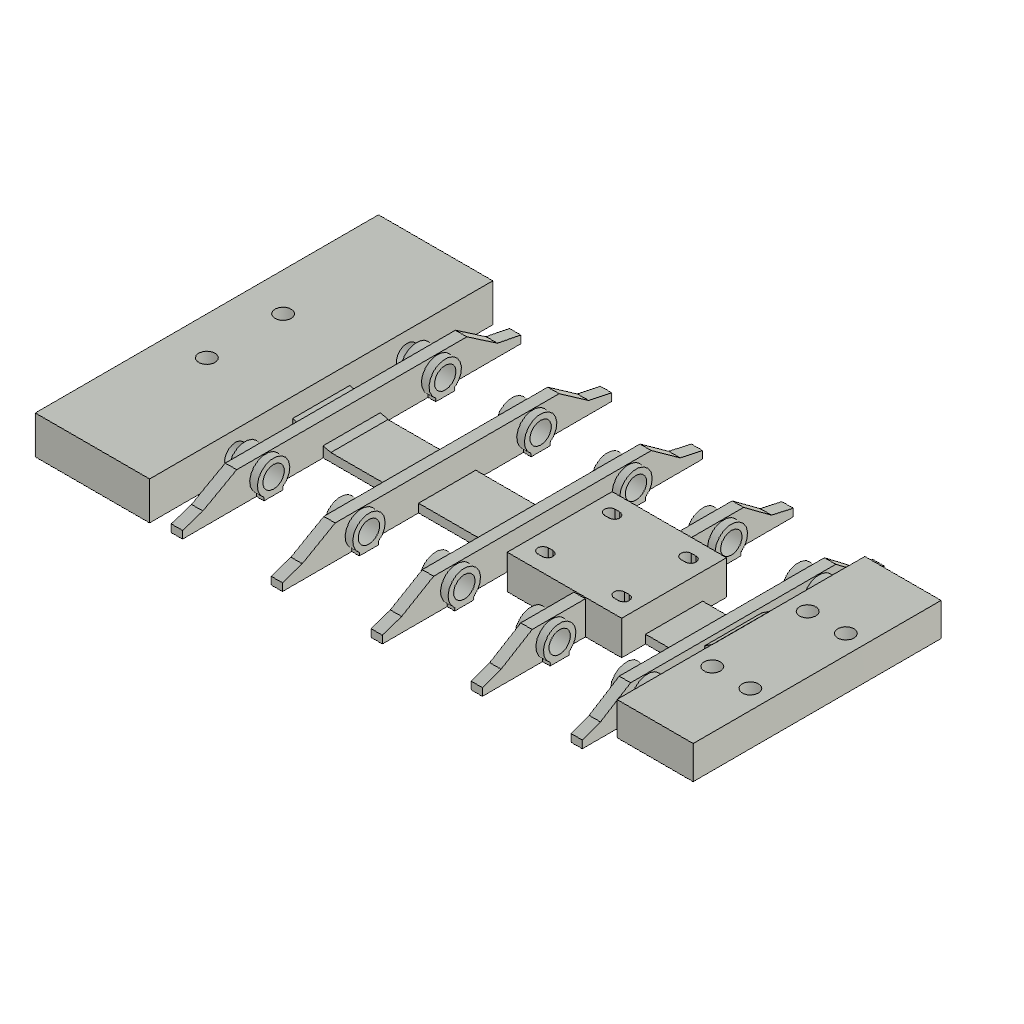
wing (Autodesk Fusion 360 design; units mm, degrees)
part number: 2026-10-10-16-37-37-965
Autodesk Fusion 360 part; units mm, degrees
sketch "Root tongue sketch" plane through (0, 0, 0) normal (0, 0, 1) x (1, 0, 0)
  line L0 (0, -36) -> (24, -36)
  line L1 (24, -36) -> (24, 36)
  line L2 (24, 36) -> (0, 36)
  line L3 (0, 36) -> (0, -36)
extrude "Root tongue" add sketch "Root tongue sketch" along normal blind 8
sketch "Continuous flat flexing gauge strip sketch" plane through (0, 0, 0) normal (0, 0, 1) x (1, 0, 0)
  line L0 (23.95, -6) -> (128, -6)
  line L1 (128, -6) -> (128, 6)
  line L2 (128, 6) -> (23.95, 6)
  line L3 (23.95, 6) -> (23.95, -6)
extrude "Continuous flat flexing gauge strip" add sketch "Continuous flat flexing gauge strip sketch" along normal blind 1.8
sketch "Root tapered strip shoulder sketch" plane through (0, 0, 0) normal (0, 1, 0) x (1, 0, 0)
  line L0 (23.95, 0) -> (32, 0)
  line L1 (32, 0) -> (32, -1.8)
  line L2 (32, -1.8) -> (23.95, -4)
  line L3 (23.95, -4) -> (23.95, 0)
extrude "Root tapered strip shoulder" add sketch "Root tapered strip shoulder sketch" along normal mid plane 12
sketch "Tip tapered strip shoulder sketch" plane through (0, 0, 0) normal (0, 1, 0) x (1, 0, 0)
  line L0 (104, 0) -> (112.05, 0)
  line L1 (112.05, 0) -> (112.05, -6.95)
  line L2 (112.05, -6.95) -> (104, -1.8)
  line L3 (104, -1.8) -> (104, 0)
extrude "Tip tapered strip shoulder" add sketch "Tip tapered strip shoulder sketch" along normal mid plane 12
ref_plane "WorkPlane1" through (28, 0, 0) normal (1, 0, 0) x (0, 1, 0)
sketch "Rib at 28 mm sketch" plane through (28, 0, 0) normal (1, 0, 0) x (0, 0, -1)
  line L0 (0, -35.4923) -> (0, 35.4923)
  line L1 (0, 35.4923) -> (-1.6, 35.4923)
  line L2 (-1.6, 35.4923) -> (-2.6, 30.5234)
  line L3 (-2.6, 30.5234) -> (-6.95, 24.1348)
  line L4 (-6.95, 24.1348) -> (-6.95, -24.1348)
  line L5 (-6.95, -24.1348) -> (-3, -31.2332)
  line L6 (-3, -31.2332) -> (-1.6, -35.4923)
  line L7 (-1.6, -35.4923) -> (0, -35.4923)
extrude "Rib at 28 mm" add sketch "Rib at 28 mm sketch" along normal blind 2.4
ref_plane "WorkPlane2" through (26, 0, 0) normal (1, 0, 0) x (0, 1, 0)
sketch "front short guide at 28 mm sketch" plane through (26, 0, 0) normal (1, 0, 0) x (0, 0, -1)
  circle A0 centre (-3.4, -18) radius 3.4
extrude "front short guide at 28 mm" add sketch "front short guide at 28 mm sketch" along normal blind 6
sketch "front guide print foot at 28 mm sketch" plane through (0, 0, 0) normal (0, 0, 1) x (1, 0, 0)
  line L0 (26, -20) -> (32, -20)
  line L1 (32, -20) -> (32, -16)
  line L2 (32, -16) -> (26, -16)
  line L3 (26, -16) -> (26, -20)
extrude "front guide print foot at 28 mm" add sketch "front guide print foot at 28 mm sketch" along normal blind 1.2
ref_plane "WorkPlane3" through (26, 0, 0) normal (1, 0, 0) x (0, 1, 0)
sketch "rear short guide at 28 mm sketch" plane through (26, 0, 0) normal (1, 0, 0) x (0, 0, -1)
  circle A0 centre (-3.4, 18) radius 3.4
extrude "rear short guide at 28 mm" add sketch "rear short guide at 28 mm sketch" along normal blind 6
sketch "rear guide print foot at 28 mm sketch" plane through (0, 0, 0) normal (0, 0, 1) x (1, 0, 0)
  line L0 (26, 16) -> (32, 16)
  line L1 (32, 16) -> (32, 20)
  line L2 (32, 20) -> (26, 20)
  line L3 (26, 20) -> (26, 16)
extrude "rear guide print foot at 28 mm" add sketch "rear guide print foot at 28 mm sketch" along normal blind 1.2
ref_plane "WorkPlane4" through (48, 0, 0) normal (1, 0, 0) x (0, 1, 0)
sketch "Rib at 48 mm sketch" plane through (48, 0, 0) normal (1, 0, 0) x (0, 0, -1)
  line L0 (0, -34.5308) -> (0, 34.5308)
  line L1 (0, 34.5308) -> (-1.6, 34.5308)
  line L2 (-1.6, 34.5308) -> (-2.6, 29.6965)
  line L3 (-2.6, 29.6965) -> (-6.95, 23.4809)
  line L4 (-6.95, 23.4809) -> (-6.95, -23.4809)
  line L5 (-6.95, -23.4809) -> (-3, -30.3871)
  line L6 (-3, -30.3871) -> (-1.6, -34.5308)
  line L7 (-1.6, -34.5308) -> (0, -34.5308)
extrude "Rib at 48 mm" add sketch "Rib at 48 mm sketch" along normal blind 2.4
ref_plane "WorkPlane5" through (46, 0, 0) normal (1, 0, 0) x (0, 1, 0)
sketch "front short guide at 48 mm sketch" plane through (46, 0, 0) normal (1, 0, 0) x (0, 0, -1)
  circle A0 centre (-3.4, -18) radius 3.4
extrude "front short guide at 48 mm" add sketch "front short guide at 48 mm sketch" along normal blind 6
sketch "front guide print foot at 48 mm sketch" plane through (0, 0, 0) normal (0, 0, 1) x (1, 0, 0)
  line L0 (46, -20) -> (52, -20)
  line L1 (52, -20) -> (52, -16)
  line L2 (52, -16) -> (46, -16)
  line L3 (46, -16) -> (46, -20)
extrude "front guide print foot at 48 mm" add sketch "front guide print foot at 48 mm sketch" along normal blind 1.2
ref_plane "WorkPlane6" through (46, 0, 0) normal (1, 0, 0) x (0, 1, 0)
sketch "rear short guide at 48 mm sketch" plane through (46, 0, 0) normal (1, 0, 0) x (0, 0, -1)
  circle A0 centre (-3.4, 18) radius 3.4
extrude "rear short guide at 48 mm" add sketch "rear short guide at 48 mm sketch" along normal blind 6
sketch "rear guide print foot at 48 mm sketch" plane through (0, 0, 0) normal (0, 0, 1) x (1, 0, 0)
  line L0 (46, 16) -> (52, 16)
  line L1 (52, 16) -> (52, 20)
  line L2 (52, 20) -> (46, 20)
  line L3 (46, 20) -> (46, 16)
extrude "rear guide print foot at 48 mm" add sketch "rear guide print foot at 48 mm sketch" along normal blind 1.2
ref_plane "WorkPlane7" through (68, 0, 0) normal (1, 0, 0) x (0, 1, 0)
sketch "Rib at 68 mm sketch" plane through (68, 0, 0) normal (1, 0, 0) x (0, 0, -1)
  line L0 (0, -33.5692) -> (0, 33.5692)
  line L1 (0, 33.5692) -> (-1.6, 33.5692)
  line L2 (-1.6, 33.5692) -> (-2.6, 28.8695)
  line L3 (-2.6, 28.8695) -> (-6.95, 22.8271)
  line L4 (-6.95, 22.8271) -> (-6.95, -22.8271)
  line L5 (-6.95, -22.8271) -> (-3, -29.5409)
  line L6 (-3, -29.5409) -> (-1.6, -33.5692)
  line L7 (-1.6, -33.5692) -> (0, -33.5692)
extrude "Rib at 68 mm" add sketch "Rib at 68 mm sketch" along normal blind 2.4
ref_plane "WorkPlane8" through (66, 0, 0) normal (1, 0, 0) x (0, 1, 0)
sketch "front short guide at 68 mm sketch" plane through (66, 0, 0) normal (1, 0, 0) x (0, 0, -1)
  circle A0 centre (-3.4, -18) radius 3.4
extrude "front short guide at 68 mm" add sketch "front short guide at 68 mm sketch" along normal blind 6
sketch "front guide print foot at 68 mm sketch" plane through (0, 0, 0) normal (0, 0, 1) x (1, 0, 0)
  line L0 (66, -20) -> (72, -20)
  line L1 (72, -20) -> (72, -16)
  line L2 (72, -16) -> (66, -16)
  line L3 (66, -16) -> (66, -20)
extrude "front guide print foot at 68 mm" add sketch "front guide print foot at 68 mm sketch" along normal blind 1.2
ref_plane "WorkPlane9" through (66, 0, 0) normal (1, 0, 0) x (0, 1, 0)
sketch "rear short guide at 68 mm sketch" plane through (66, 0, 0) normal (1, 0, 0) x (0, 0, -1)
  circle A0 centre (-3.4, 18) radius 3.4
extrude "rear short guide at 68 mm" add sketch "rear short guide at 68 mm sketch" along normal blind 6
sketch "rear guide print foot at 68 mm sketch" plane through (0, 0, 0) normal (0, 0, 1) x (1, 0, 0)
  line L0 (66, 16) -> (72, 16)
  line L1 (72, 16) -> (72, 20)
  line L2 (72, 20) -> (66, 20)
  line L3 (66, 20) -> (66, 16)
extrude "rear guide print foot at 68 mm" add sketch "rear guide print foot at 68 mm sketch" along normal blind 1.2
ref_plane "WorkPlane10" through (88, 0, 0) normal (1, 0, 0) x (0, 1, 0)
sketch "Rib at 88 mm sketch" plane through (88, 0, 0) normal (1, 0, 0) x (0, 0, -1)
  line L0 (0, -32.6077) -> (0, 32.6077)
  line L1 (0, 32.6077) -> (-1.6, 32.6077)
  line L2 (-1.6, 32.6077) -> (-2.6, 28.0426)
  line L3 (-2.6, 28.0426) -> (-6.95, 22.1732)
  line L4 (-6.95, 22.1732) -> (-6.95, -22.1732)
  line L5 (-6.95, -22.1732) -> (-3, -28.6948)
  line L6 (-3, -28.6948) -> (-1.6, -32.6077)
  line L7 (-1.6, -32.6077) -> (0, -32.6077)
extrude "Rib at 88 mm" add sketch "Rib at 88 mm sketch" along normal blind 2.4
ref_plane "WorkPlane11" through (86, 0, 0) normal (1, 0, 0) x (0, 1, 0)
sketch "front short guide at 88 mm sketch" plane through (86, 0, 0) normal (1, 0, 0) x (0, 0, -1)
  circle A0 centre (-3.4, -18) radius 3.4
extrude "front short guide at 88 mm" add sketch "front short guide at 88 mm sketch" along normal blind 6
sketch "front guide print foot at 88 mm sketch" plane through (0, 0, 0) normal (0, 0, 1) x (1, 0, 0)
  line L0 (86, -20) -> (92, -20)
  line L1 (92, -20) -> (92, -16)
  line L2 (92, -16) -> (86, -16)
  line L3 (86, -16) -> (86, -20)
extrude "front guide print foot at 88 mm" add sketch "front guide print foot at 88 mm sketch" along normal blind 1.2
ref_plane "WorkPlane12" through (86, 0, 0) normal (1, 0, 0) x (0, 1, 0)
sketch "rear short guide at 88 mm sketch" plane through (86, 0, 0) normal (1, 0, 0) x (0, 0, -1)
  circle A0 centre (-3.4, 18) radius 3.4
extrude "rear short guide at 88 mm" add sketch "rear short guide at 88 mm sketch" along normal blind 6
sketch "rear guide print foot at 88 mm sketch" plane through (0, 0, 0) normal (0, 0, 1) x (1, 0, 0)
  line L0 (86, 16) -> (92, 16)
  line L1 (92, 16) -> (92, 20)
  line L2 (92, 20) -> (86, 20)
  line L3 (86, 20) -> (86, 16)
extrude "rear guide print foot at 88 mm" add sketch "rear guide print foot at 88 mm sketch" along normal blind 1.2
ref_plane "WorkPlane13" through (108, 0, 0) normal (1, 0, 0) x (0, 1, 0)
sketch "Rib at 108 mm sketch" plane through (108, 0, 0) normal (1, 0, 0) x (0, 0, -1)
  line L0 (0, -31.6462) -> (0, 31.6462)
  line L1 (0, 31.6462) -> (-1.6, 31.6462)
  line L2 (-1.6, 31.6462) -> (-2.6, 27.2157)
  line L3 (-2.6, 27.2157) -> (-6.95, 21.5194)
  line L4 (-6.95, 21.5194) -> (-6.95, -21.5194)
  line L5 (-6.95, -21.5194) -> (-3, -27.8486)
  line L6 (-3, -27.8486) -> (-1.6, -31.6462)
  line L7 (-1.6, -31.6462) -> (0, -31.6462)
extrude "Rib at 108 mm" add sketch "Rib at 108 mm sketch" along normal blind 2.4
ref_plane "WorkPlane14" through (106, 0, 0) normal (1, 0, 0) x (0, 1, 0)
sketch "front short guide at 108 mm sketch" plane through (106, 0, 0) normal (1, 0, 0) x (0, 0, -1)
  circle A0 centre (-3.4, -18) radius 3.4
extrude "front short guide at 108 mm" add sketch "front short guide at 108 mm sketch" along normal blind 6
sketch "front guide print foot at 108 mm sketch" plane through (0, 0, 0) normal (0, 0, 1) x (1, 0, 0)
  line L0 (106, -20) -> (112, -20)
  line L1 (112, -20) -> (112, -16)
  line L2 (112, -16) -> (106, -16)
  line L3 (106, -16) -> (106, -20)
extrude "front guide print foot at 108 mm" add sketch "front guide print foot at 108 mm sketch" along normal blind 1.2
ref_plane "WorkPlane15" through (106, 0, 0) normal (1, 0, 0) x (0, 1, 0)
sketch "rear short guide at 108 mm sketch" plane through (106, 0, 0) normal (1, 0, 0) x (0, 0, -1)
  circle A0 centre (-3.4, 18) radius 3.4
extrude "rear short guide at 108 mm" add sketch "rear short guide at 108 mm sketch" along normal blind 6
sketch "rear guide print foot at 108 mm sketch" plane through (0, 0, 0) normal (0, 0, 1) x (1, 0, 0)
  line L0 (106, 16) -> (112, 16)
  line L1 (112, 16) -> (112, 20)
  line L2 (112, 20) -> (106, 20)
  line L3 (106, 20) -> (106, 16)
extrude "rear guide print foot at 108 mm" add sketch "rear guide print foot at 108 mm sketch" along normal blind 1.2
sketch "Tip load landing sketch" plane through (0, 0, 0) normal (0, 0, 1) x (1, 0, 0)
  line L0 (112, -26) -> (128, -26)
  line L1 (128, -26) -> (128, 26)
  line L2 (128, 26) -> (112, 26)
  line L3 (112, 26) -> (112, -26)
extrude "Tip load landing" add sketch "Tip load landing sketch" along normal blind 6.95
sketch "MPU strap landing sketch" plane through (0, 0, 0) normal (0, 0, 1) x (1, 0, 0)
  line L0 (74, -11) -> (98, -11)
  line L1 (98, -11) -> (98, 11)
  line L2 (98, 11) -> (74, 11)
  line L3 (74, 11) -> (74, -11)
extrude "MPU strap landing" add sketch "MPU strap landing sketch" along normal blind 7.2
ref_plane "WorkPlane16" through (-0.05, 0, 0) normal (1, 0, 0) x (0, 1, 0)
sketch "front 4mm bamboo passage sketch" plane through (-0.05, 0, 0) normal (1, 0, 0) x (0, 0, -1)
  circle A0 centre (-3.4, -18) radius 2.25
  dimension "d103" = 4.5
  measures "d103" diameter of A0
extrude "front 4mm bamboo passage" cut sketch "front 4mm bamboo passage sketch" along normal blind 126.05
ref_plane "WorkPlane17" through (-0.05, 0, 0) normal (1, 0, 0) x (0, 1, 0)
sketch "rear 4mm bamboo passage sketch" plane through (-0.05, 0, 0) normal (1, 0, 0) x (0, 0, -1)
  circle A0 centre (-3.4, 18) radius 2.25
  dimension "d108" = 4.5
  measures "d108" diameter of A0
extrude "rear 4mm bamboo passage" cut sketch "rear 4mm bamboo passage sketch" along normal blind 126.05
ref_plane "WorkPlane18" through (0, 0, -0.05) normal (0, 0, 1) x (1, 0, 0)
sketch "Root registration -8 sketch" plane through (0, 0, -0.05) normal (0, 0, 1) x (1, 0, 0)
  circle A0 centre (8, -8) radius 1.7
  dimension "d113" = 3.4
  measures "d113" diameter of A0
extrude "Root registration -8" cut sketch "Root registration -8 sketch" along normal blind 8.1
ref_plane "WorkPlane19" through (0, 0, -0.05) normal (0, 0, 1) x (1, 0, 0)
sketch "Root registration 8 sketch" plane through (0, 0, -0.05) normal (0, 0, 1) x (1, 0, 0)
  circle A0 centre (8, 8) radius 1.7
  dimension "d118" = 3.4
  measures "d118" diameter of A0
extrude "Root registration 8" cut sketch "Root registration 8 sketch" along normal blind 8.1
ref_plane "WorkPlane20" through (0, 0, -0.05) normal (0, 0, 1) x (1, 0, 0)
sketch "Tip bolt 116 -10 sketch" plane through (0, 0, -0.05) normal (0, 0, 1) x (1, 0, 0)
  circle A0 centre (116, -10) radius 1.7
  dimension "d123" = 3.4
  measures "d123" diameter of A0
extrude "Tip bolt 116 -10" cut sketch "Tip bolt 116 -10 sketch" along normal blind 7.05
ref_plane "WorkPlane21" through (0, 0, -0.05) normal (0, 0, 1) x (1, 0, 0)
sketch "Tip bolt 116 10 sketch" plane through (0, 0, -0.05) normal (0, 0, 1) x (1, 0, 0)
  circle A0 centre (116, 10) radius 1.7
  dimension "d128" = 3.4
  measures "d128" diameter of A0
extrude "Tip bolt 116 10" cut sketch "Tip bolt 116 10 sketch" along normal blind 7.05
ref_plane "WorkPlane22" through (0, 0, -0.05) normal (0, 0, 1) x (1, 0, 0)
sketch "Tip bolt 124 -10 sketch" plane through (0, 0, -0.05) normal (0, 0, 1) x (1, 0, 0)
  circle A0 centre (124, -10) radius 1.7
  dimension "d133" = 3.4
  measures "d133" diameter of A0
extrude "Tip bolt 124 -10" cut sketch "Tip bolt 124 -10 sketch" along normal blind 7.05
ref_plane "WorkPlane23" through (0, 0, -0.05) normal (0, 0, 1) x (1, 0, 0)
sketch "Tip bolt 124 10 sketch" plane through (0, 0, -0.05) normal (0, 0, 1) x (1, 0, 0)
  circle A0 centre (124, 10) radius 1.7
  dimension "d138" = 3.4
  measures "d138" diameter of A0
extrude "Tip bolt 124 10" cut sketch "Tip bolt 124 10 sketch" along normal blind 7.05
ref_plane "WorkPlane24" through (0, 0, -0.05) normal (0, 0, 1) x (1, 0, 0)
sketch "Board tie 78 -7 sketch" plane through (0, 0, -0.05) normal (0, 0, 1) x (1, 0, 0)
  arc A0 (77.5, -5.9) -> (77.5, -8.1) centre (77.5, -7) ccw
  line L0 (77.5, -5.9) -> (78.5, -5.9)
  arc A1 (78.5, -8.1) -> (78.5, -5.9) centre (78.5, -7) ccw
  line L1 (78.5, -8.1) -> (77.5, -8.1)
extrude "Board tie 78 -7" cut sketch "Board tie 78 -7 sketch" along normal blind 7.3
ref_plane "WorkPlane25" through (0, 0, -0.05) normal (0, 0, 1) x (1, 0, 0)
sketch "Board tie 78 7 sketch" plane through (0, 0, -0.05) normal (0, 0, 1) x (1, 0, 0)
  arc A0 (77.5, 8.1) -> (77.5, 5.9) centre (77.5, 7) ccw
  line L0 (77.5, 8.1) -> (78.5, 8.1)
  arc A1 (78.5, 5.9) -> (78.5, 8.1) centre (78.5, 7) ccw
  line L1 (78.5, 5.9) -> (77.5, 5.9)
extrude "Board tie 78 7" cut sketch "Board tie 78 7 sketch" along normal blind 7.3
ref_plane "WorkPlane26" through (0, 0, -0.05) normal (0, 0, 1) x (1, 0, 0)
sketch "Board tie 94 -7 sketch" plane through (0, 0, -0.05) normal (0, 0, 1) x (1, 0, 0)
  arc A0 (93.5, -5.9) -> (93.5, -8.1) centre (93.5, -7) ccw
  line L0 (93.5, -5.9) -> (94.5, -5.9)
  arc A1 (94.5, -8.1) -> (94.5, -5.9) centre (94.5, -7) ccw
  line L1 (94.5, -8.1) -> (93.5, -8.1)
extrude "Board tie 94 -7" cut sketch "Board tie 94 -7 sketch" along normal blind 7.3
ref_plane "WorkPlane27" through (0, 0, -0.05) normal (0, 0, 1) x (1, 0, 0)
sketch "Board tie 94 7 sketch" plane through (0, 0, -0.05) normal (0, 0, 1) x (1, 0, 0)
  arc A0 (93.5, 8.1) -> (93.5, 5.9) centre (93.5, 7) ccw
  line L0 (93.5, 8.1) -> (94.5, 8.1)
  arc A1 (94.5, 5.9) -> (94.5, 8.1) centre (94.5, 7) ccw
  line L1 (94.5, 5.9) -> (93.5, 5.9)
extrude "Board tie 94 7" cut sketch "Board tie 94 7 sketch" along normal blind 7.3
equation "d9 = rootThickness"
equation "d11 = gaugeBeamThickness"
equation "d99 = mpuPadThickness"
equation "d103 = sparBore"
equation "d108 = sparBore"
equation "d113 = m3Clearance"
equation "d118 = m3Clearance"
equation "d123 = m3Clearance"
equation "d128 = m3Clearance"
equation "d133 = m3Clearance"
equation "d138 = m3Clearance"
equation "sparDiameter = 4 mm" comment "Nominal bamboo diameter; choose clearance with fit coupon"
equation "sparClearance = 0.5 mm" comment "Diametral clearance; 4.5 mm coupon fit selected by user"
equation "sparBore = sparDiameter + sparClearance" comment "Drives BOTH native spar channel sketches"
equation "m3Clearance = 3.4 mm" comment "Root registration and tip adapter holes"
equation "rootThickness = 8 mm" comment "Root tongue extrusion; reposition cap if changed"
equation "gaugeBeamThickness = 1.8 mm" comment "Continuous flexing gauge strip; physical response needs testing"
equation "mpuPadThickness = 7.2 mm" comment "Raised pad clears the 6.95 mm rib tops"
named bodies: "wing - printable solid"
